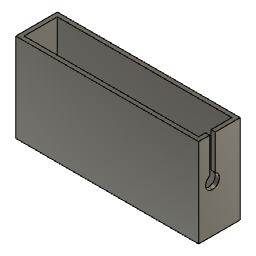
sensor_cap_2024-10-13 (Autodesk Fusion 360 design; units mm, degrees)
Autodesk Fusion 360 part; units mm, degrees
sketch "스케치1" plane through (0, 0, 0) normal (0, 0, 1) x (1, 0, 0)
  line L0 (0, 0) -> (66, 0)
  line L1 (0, 15) -> (0, 0)
  line L2 (66, 15) -> (66, 0)
  line L3 (0, 15) -> (66, 15)
  constraint horizontal L0
  constraint vertical L1
  constraint vertical L2
  constraint coincident L1 L0.start
  constraint horizontal L3
  constraint coincident L0 L1.end
extrude "돌출1" add sketch "스케치1" along normal blind 2
sketch "스케치2" plane through (0, 0, 2) normal (0, 0, 1) x (-1, 0, 0)
  line L0 (0, 0) -> (-66, 0)
  line L1 (-66, 0) -> (-66, -15)
  line L2 (-66, -15) -> (0, -15)
  line L3 (0, -15) -> (0, 0)
  line L4 (0, 0) -> (-66, 0)
  line L5 (-1.5, -1.5) -> (-64.5, -1.5)
  line L6 (0, -15) -> (-66, -15)
  line L7 (-1.5, -13.5) -> (-64.5, -13.5)
  line L8 (0, -15) -> (0, 0)
  line L9 (-1.5, -13.5) -> (-1.5, -1.5)
  line L10 (-66, -15) -> (-66, 0)
  line L11 (-64.5, -13.5) -> (-64.5, -1.5)
  constraint coincident L0.start L3.end
  constraint coincident L0.end L1.start
  constraint coincident L2.end L3.start
  constraint coincident L1.end L2.start
  constraint perpendicular L5 L8
  constraint coincident L0 L3.end
extrude "돌출2" add sketch "스케치2" along normal blind 30
sketch "스케치3" plane through (66, 0, 0) normal (1, 0, 0) x (0, 1, 0)
  line L0 (0, 0) -> (15, 0)
  line L1 (15, 0) -> (15, 32)
  line L2 (15, 32) -> (0, 32)
  line L3 (0, 32) -> (0, 0)
  line L4 (4, 32) -> (6, 32)
  line L5 (6, 19.2913) -> (6, 32)
  line L6 (4, 19.2913) -> (4, 32)
  arc A0 (4, 19.2913) -> (6, 19.2913) centre (5, 17) ccw
  line L7 (5, 0) -> (5, -5)
  dimension "d7" = 5
  constraint coincident L0 L7.start
  measures "d7" diameter of A0
extrude "돌출3" cut sketch "스케치3" against normal blind 1.5 contours L2 L4 L5 L6 A0
